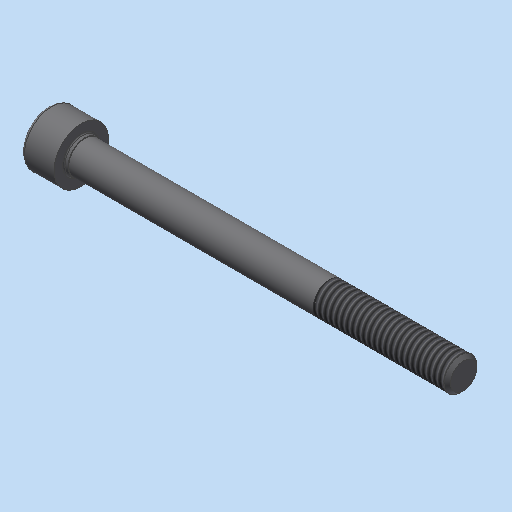
# Autodesk Inventor part: Zylinderschraube_ISO_4762___M6x70
Saved by Autodesk Inventor 2023.3 (Build 273359000, 359)
## iProperties
Shininess: 64.0
Length Units: 11269
Angle Units: 11279
Time Units: 11290
Mass Units: 11283
Length Display Precision: 3
Angle Display Precision: 2
Compacted: True
Part Number: Zylinderschraube_ISO_4762___M6x70
Document SubType Name: Modeling
Created: 2004-04-03
Material: xStahl_AnP_Dummymaterial
Description: =<RBPARTNOTITLE2>
Vendor: NORM8
Manufacturer: Standard
Standards Organization: Custom
Density: 7.85 g/cm^3
Appearance: Stahl - normal AnP
Mass: 18.4957 g
Surface Area: 17.1028 cm^2
Volume: 2.35613 cm^3
DOC_ID: 5 F45 Zylinderschraube_ISO_4762___M6x70
GAIN_REFID: 20__Zylinderschraube_ISO_4762___M6x70:3B611
Control State: 0
Master: False
Checked Out: False
RBPARTNOTITLE2: Zylinderschrauben mit Innensechskant
RBPARTNOTITLE1: Hexagon socket head cap screws
AnP_Kategorie: 4
RBDRAWINGMISSINGSPEC: --
RBPARTMADEOF: ISO 4762 - M6x70 - 8.8 verzinkt
Density: 0.0
Volumn: 0.0
Area: 0.0
PropertySet Name: Model Information
Title: Zylinderschraube ISO 4762 - M6x70
Keywords: =<RBPARTMADEOF>
Comments: =<RBSURFACE2>
Revision Number: 01
Autodesk Inventor part; units mm, degrees
sketch "Sketch_1" plane through (0, 0, 0) normal (0, 1, 0) x (-1, 0, 0)
  line L0 (-73, 0) -> (9, 0)
  line L1 (0.8566, 0) -> (2.3, -2.5)
  line L2 (2.3, -2.5) -> (5.64, -2.5)
  line L3 (5.64, -2.5) -> (6, -2.86)
  line L4 (6, -2.86) -> (6, -4.4)
  arc A0 (5.4, -5) -> (6, -4.4) centre (5.4, -4.4) ccw
  line L5 (5.4, -5) -> (0, -5)
  line L6 (0, -5) -> (0, -3.4)
  arc A1 (0, -3.4) -> (-0.1677, -3.1639) centre (-0.25, -3.4) ccw
  line L7 (-0.1677, -3.1639) -> (-0.5977, -3.0139)
  arc A2 (-0.5977, -3.0139) -> (-0.68, -3) centre (-0.68, -3.25) ccw
  line L8 (-0.68, -3) -> (-69.3865, -3)
  line L9 (-69.3865, -3) -> (-70, -2.3865)
  line L10 (-70, -2.3865) -> (-70, 0)
  line L11 (-70, 0) -> (0.8566, 0)
  constraints: 24 end point, 6 point on circle, 3 centre point
revolve "Drehung1" add sketch "Sketch_1" angle 360 about axis through (73, 0, 0) along (1, 0, 0)
thread "Gewinde1" size "M6x1" class "6g" standard "ANSI Metrisches M Profil" length 24
sketch "Skizze_1" plane through (-2.3, 0, 0) normal (1, 0, 0) x (0, 0, -1)
  line L0 (-2.5, 1.4434) -> (-2.5, -1.4434)
  line L1 (-2.5, -1.4434) -> (0, -2.8868)
  line L2 (0, -2.8868) -> (2.5, -1.4434)
  line L3 (2.5, -1.4434) -> (2.5, 1.4434)
  line L4 (2.5, 1.4434) -> (0, 2.8868)
  line L5 (0, 2.8868) -> (-2.5, 1.4434)
  constraints: 12 end point
extrude "Extrusion1" cut sketch "Skizze_1" against normal blind 6
ref_plane "IP1_XY" through (0, 0, 0) normal (1, 0, 0) x (0, 0, -1)
ref_plane "IP1_YZ" through (0, 0, 0) normal (0, 0, -1) x (0, 1, 0)
ref_plane "IP3_XY" through (60, 0, 0) normal (1, 0, 0) x (0, 0, -1)
ref_plane "IP3_YZ" through (60, 0, 0) normal (0, 0, -1) x (0, 1, 0)
ref_plane "IP2_XY" through (-6, 0, 0) normal (1, 0, 0) x (0, 0, -1)
ref_plane "IP2_YZ" through (-6, 0, 0) normal (0, 0, -1) x (0, 1, 0)
